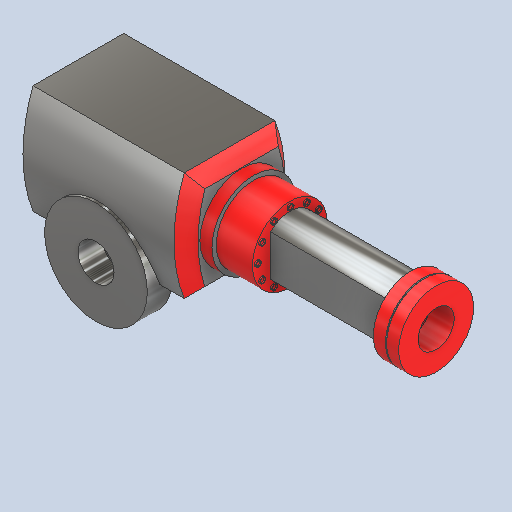
# Autodesk Inventor part: 4
Saved by Autodesk Inventor 2027.1 (Build 311270010, 270A)
## iProperties
Part Number: 4
Material: Allgemein
Document SubType Name: Modellieren
Designer: Asus
Appearance: Chrom - poliert
Author: Asus
Autodesk Inventor part; units mm, degrees
ref_plane "YZ-Ebene" through (0, 0, 0) normal (1, 0, 0) x (0, 1, 0)
ref_plane "XZ-Ebene" through (0, 0, 0) normal (0, 1, 0) x (-1, 0, 0)
sketch "Skizze1" plane through (0, 0, 0) normal (0, 0, 1) x (1, 0, 0)
  line L0 (-37.5, -45) -> (37.5, -45)
  line L1 (37.5, -45) -> (37.5, 45) construction
  line L2 (37.5, 45) -> (-37.5, 45)
  line L3 (-37.5, 45) -> (-37.5, -45) construction
  line L4 (-37.5, -45) -> (37.5, 45) construction
  line L5 (37.5, -45) -> (-37.5, 45) construction
  arc A0 (37.5, -45) -> (37.5, 45) centre (-79.119, 0) ccw
  arc A1 (-37.5, 45) -> (-37.5, -45) centre (79.119, 0) ccw
  point P0 (0, 0)
  dimension "d0" = 75
  dimension "d1" = 90
  dimension "d2" = 125
  dimension "d3" = 125
  constraints: 12 end point, 4 point on circle, 2 centre point, 2 midpoint, 2 parallel, 1 horizontal, 1 perpendicular
  measures "d0" distance of L2.end L1.end
  measures "d1" distance of L1.end L0.end
  measures "d2" radius of A0
  measures "d3" radius of A1
extrude "Extrusion1" add sketch "Skizze1" along normal blind 125
sketch "Skizze2" plane through (0, 0, 125) normal (0, 0, 1) x (1, 0, 0)
  arc A0 (37.5, -45) -> (37.5, 45) centre (-79.119, 0) ccw projected
  line L0 (37.5, 45) -> (-37.5, 45) projected
  arc A1 (-37.5, 45) -> (-37.5, -45) centre (79.119, 0) ccw projected
  line L1 (-37.5, -45) -> (37.5, -45) projected
  point P0 (0, 0)
extrude "Extrusion2" add sketch "Skizze2" along normal blind 10 draft -45
sketch "Skizze3" plane through (0, 0, 135) normal (0, 0, 1) x (1, 0, 0)
  circle A0 centre (0, 0) radius 34.5
  dimension "d8" = 69
  constraints: 1 centre point, 1 coincident
  measures "d8" diameter of A0
extrude "Extrusion3" add sketch "Skizze3" along normal blind 10
sketch "Skizze4" plane through (0, 0, 145) normal (0, 0, 1) x (1, 0, 0)
  circle A0 centre (0, 0) radius 31
  dimension "d11" = 62
  constraints: 1 centre point, 1 coincident
  measures "d11" diameter of A0
extrude "Extrusion4" add sketch "Skizze4" along normal blind 30
sketch "Skizze5" plane through (0, 0, 175) normal (0, 0, 1) x (1, 0, 0)
  circle A0 centre (27, 0) radius 2.5
  circle A1 centre (27, 0) radius 2
  point P0 (0, 0)
  dimension "d14" = 27
  dimension "d15" = 5
  dimension "d16" = 4
  constraints: 2 centre point, 1 coincident, 1 horizontal alignment
  measures "d14" distance of point (0, 0) A0.centre
  measures "d15" diameter of A0
  measures "d16" diameter of A1
extrude "Extrusion5" add sketch "Skizze5" along normal blind 1
pattern_circular "Runde Anordnung1" count 12 over 360 about axis through (0, 0, 145) along (0, 0, 1) of "Extrusion5"
sketch "Skizze6" plane through (0, 0, 175) normal (0, 0, 1) x (1, 0, 0)
  line L0 (16, 17) -> (-16, 17)
  line L1 (-16, 17) -> (-16, -17)
  line L2 (-16, -17) -> (16, -17)
  line L3 (16, -17) -> (16, 17)
  line L4 (16, 17) -> (-16, -17) construction
  line L5 (-16, 17) -> (16, -17) construction
  arc A0 (16, 17) -> (-16, 17) centre (0, 1.9003) ccw
  arc A1 (-16, -17) -> (16, -17) centre (0, -1.9003) ccw
  point P0 (0, 0)
  dimension "d22" = 32
  dimension "d23" = 34
  dimension "d24" = 22
  dimension "d25" = 22
  constraints: 12 end point, 4 point on circle, 2 centre point, 2 midpoint, 2 parallel, 1 horizontal, 1 perpendicular
  measures "d22" distance of L2.end L1.end
  measures "d23" distance of L1.end L0.end
  measures "d24" radius of A0
  measures "d25" radius of A1
extrude "Extrusion6" add sketch "Skizze6" along normal blind 100
sketch "Skizze7" plane through (0, 0, 275) normal (0, 0, 1) x (1, 0, 0)
  circle A0 centre (0, 0) radius 31
  dimension "d28" = 62
  constraints: 1 centre point, 1 coincident
  measures "d28" diameter of A0
extrude "Extrusion7" add sketch "Skizze7" along normal blind 10
sketch "Skizze8" plane through (0, 0, 285) normal (0, 0, 1) x (1, 0, 0)
  circle A0 centre (0, 0) radius 31 construction
  circle A1 centre (0, 0) radius 30
  dimension "d31" = 1
  constraints: 1 centre point
  measures "d31" radial gap between concentric circles of A0 A1
extrude "Extrusion8" add sketch "Skizze8" along normal blind 1
sketch "Skizze9" plane through (0, 0, 286) normal (0, 0, 1) x (1, 0, 0)
  circle A0 centre (0, 0) radius 31 projected
extrude "Extrusion9" add sketch "Skizze9" along normal blind 10
ref_plane "Arbeitsebene1" through (-37.5, 45, 125) normal (-1, 0, 0) x (0, -1, 0)
sketch "Skizze10" plane through (-37.5, 45, 125) normal (-1, 0, 0) x (0, -1, 0)
  line L0 (90, 0) -> (90, -125) construction
  line L1 (90, -125) -> (0, -125) construction
  line L2 (0, -125) -> (0, 0) construction
  circle A0 centre (90, -62.5) radius 42.5
  point P0 (45, -125)
  dimension "d36" = 85
  constraints: 1 centre point, 1 horizontal alignment, 1 midpoint
  measures "d36" diameter of A0
extrude "Extrusion10" add sketch "Skizze10" along normal mid plane 21
sketch "Skizze11" plane through (-27, 45, 125) normal (1, 0, 0) x (0, 0, -1)
  line L0 (-150, -29.7685) -> (-150, -60.2315) construction
  line L1 (-150, -60.2315) -> (-160, -60.2315) construction
  line L2 (-160, -60.2315) -> (-160, -58.0767) construction
  line L3 (-160, -58.0767) -> (-161, -58.0767) construction
  line L4 (-161, -58.0767) -> (-161, -60.2315) construction
  line L5 (-161, -60.2315) -> (-171, -60.2315) construction
  line L6 (-171, -60.2315) -> (-171, -29.7685) construction
  line L7 (-171, -29.7685) -> (-161, -29.7685) construction
  line L8 (-161, -29.7685) -> (-161, -31.9233) construction
  line L9 (-161, -31.9233) -> (-160, -31.9233) construction
  line L10 (-160, -31.9233) -> (-160, -29.7685) construction
  line L11 (-160, -29.7685) -> (-150, -29.7685) construction
  line L12 (0, -90) -> (-10, -80) construction
  line L13 (-10, -80) -> (-10, -66.4767) construction
  line L14 (-10, -66.4767) -> (-20, -66.4767) construction
  line L15 (-20, -66.4767) -> (-20, -60.2315) construction
  line L16 (-20, -60.2315) -> (-50, -60.2315) construction
  line L17 (-50, -60.2315) -> (-50, -47.5) construction
  line L18 (-50, -47.5) -> (-51, -47.5) construction
  line L19 (-51, -47.5) -> (-51, -47) construction
  line L20 (-51, -47) -> (-50, -47) construction
  line L21 (-50, -47) -> (-50, -43) construction
  line L22 (-50, -43) -> (-51, -43) construction
  line L23 (-51, -43) -> (-51, -42.5) construction
  line L24 (-51, -42.5) -> (-50, -42.5) construction
  line L25 (-50, -42.5) -> (-50, -29.7685) construction
  line L26 (-50, -29.7685) -> (-20, -29.7685) construction
  line L27 (-20, -29.7685) -> (-20, -23.5233) construction
  line L28 (-20, -23.5233) -> (-10, -23.5233) construction
  line L29 (-10, -23.5233) -> (-10, -10) construction
  line L30 (-10, -10) -> (0, 0) construction
  line L31 (0, 0) -> (125, 0) construction
  line L32 (125, 0) -> (125, -90) construction
  line L33 (125, -90) -> (105, -90) construction
  arc A0 (20, -90) -> (105, -90) centre (62.5, -90) ccw construction
  line L34 (20, -90) -> (0, -90) construction
  line L35 (20, -90) -> (105, -90) construction
  line L36 (42.5, -90) -> (82.5, -90)
  line L37 (42.5, -90) -> (42.5, -120)
  line L38 (82.5, -90) -> (82.5, -120)
  arc A1 (42.5, -120) -> (82.5, -120) centre (62.5, -97.6393) ccw
  point P0 (125, -45)
  dimension "d39" = 40
  dimension "d40" = 30
  dimension "d41" = 30
  dimension "d42" = 30
  constraints: 6 end point, 2 midpoint, 2 perpendicular, 2 point on circle, 1 centre point, 1 horizontal
  measures "d39" distance of L36.start L36.end
  measures "d40" distance of L36.start L37.end
  measures "d41" distance of L36.end L38.end
  measures "d42" radius of A1
extrude "Extrusion11" add sketch "Skizze11" along normal blind 35
sketch "Skizze12" plane through (-27, -75, 82.5) normal (0, 0, 1) x (1, 0, 0)
  line L0 (-21, 67.5) -> (-18.6558, 67.5) construction
  arc A0 (-10.5, 120) -> (-18.6558, 67.5) centre (106.119, 75) ccw construction
  line L1 (-10.5, 120) -> (64.5, 120) construction
  arc A1 (64.5, 30) -> (64.5, 120) centre (-52.119, 75) ccw construction
  line L2 (64.5, 30) -> (35, 30) construction
  line L3 (0, 30) -> (35, 30) construction
  line L4 (0, 0) -> (0, 30) construction
  line L5 (0, 0) -> (0, -7.5) construction
  line L6 (0, -7.5) -> (-21, -7.5) construction
  line L7 (-21, -7.5) -> (-21, 67.5) construction
  line L8 (35, 30) -> (35, 0) construction
  line L9 (35, 0) -> (0, 0) construction
  line L10 (35, 30) -> (60, 30)
  line L11 (35, 0) -> (35, 30) projected
  line L12 (35, 30) -> (35, -12)
  line L13 (35, -7.6393) -> (35, 0) projected
  arc A2 (35, -12) -> (60, 30) centre (5.1607, 34.2019) ccw
  point P0 (27, 75)
  dimension "d45" = 25
  dimension "d46" = 42
  dimension "d47" = 55
  constraints: 4 end point, 2 point on circle, 1 centre point, 1 collinear, 1 point on line
  measures "d45" distance of L2.end L10.end
  measures "d46" distance of L2.end L12.end
  measures "d47" radius of A2
extrude "Extrusion12" add sketch "Skizze12" against normal blind 40
sketch "Skizze13" plane through (8, -87, 82.5) normal (-1, 0, 0) x (0, 0, 1)
  arc A0 (-40, 12) -> (0, 12) centre (-20, 34.3607) ccw projected
  line L0 (-40, 0) -> (-40, 12) projected
  line L1 (0, 0) -> (-40, 0) projected
  line L2 (0, 12) -> (0, 0) projected
  point P0 (-82.5, 87)
extrude "Extrusion13" cut sketch "Skizze13" against normal blind 40
sketch "Skizze14" plane through (0, 0, 296) normal (0, 0, 1) x (1, 0, 0)
  circle A0 centre (0, 0) radius 15
  dimension "d52" = 30
  constraints: 1 centre point, 1 coincident
  measures "d52" diameter of A0
sketch "Skizze15" plane through (-48, -45, 62.5) normal (-1, 0, 0) x (0, 0, 1)
  line L0 (20, 0) -> (-20, 0) construction
  circle A0 centre (0, 0) radius 15
  point P0 (-62.5, 45)
  dimension "d53" = 30
  constraints: 1 centre point, 1 midpoint
  measures "d53" diameter of A0
extrude "Extrusion14" cut sketch "Skizze15" against normal blind 20
extrude "Extrusion15" cut sketch "Skizze14" against normal blind 20
